Autodesk Fusion 360 part; units mm, degrees
(part 24 of 28)
  line L1680 (23.605, 52.1978, -1.4859) -> (23.605, 54.4322, -1.4859)
  line L1681 (23.605, 54.4322, -1.4859) -> (23.6209, 54.5414, -1.4859)
  line L1682 (23.6209, 54.5414, -1.4859) -> (23.6763, 54.6546, -1.4859)
  line L1683 (23.6763, 54.6546, -1.4859) -> (23.7654, 54.7437, -1.4859)
  line L1684 (23.7654, 54.7437, -1.4859) -> (23.8786, 54.7991, -1.4859)
  line L1685 (23.8786, 54.7991, -1.4859) -> (23.9878, 54.815, -1.4859)
  line L1686 (23.9878, 54.815, -1.4859) -> (25.6722, 54.815, -1.4859)
  line L1687 (25.6722, 54.815, -1.4859) -> (25.7814, 54.7991, -1.4859)
  line L1688 (60.7064, 54.7991, -1.4859) -> (60.8196, 54.7437, -1.4859)
  line L1689 (60.8196, 54.7437, -1.4859) -> (60.9087, 54.6546, -1.4859)
  line L1690 (60.9087, 54.6546, -1.4859) -> (60.9641, 54.5414, -1.4859)
  line L1691 (60.9641, 54.5414, -1.4859) -> (60.98, 54.4322, -1.4859)
  line L1692 (60.98, 54.4322, -1.4859) -> (60.98, 52.1978, -1.4859)
  line L1693 (60.98, 52.1978, -1.4859) -> (60.9641, 52.0886, -1.4859)
  line L1694 (60.9641, 52.0886, -1.4859) -> (60.9087, 51.9754, -1.4859)
  line L1695 (60.9087, 51.9754, -1.4859) -> (60.8196, 51.8863, -1.4859)
  line L1696 (60.8196, 51.8863, -1.4859) -> (60.7064, 51.8309, -1.4859)
  line L1697 (60.7064, 51.8309, -1.4859) -> (60.5972, 51.815, -1.4859)
  line L1698 (60.5972, 51.815, -1.4859) -> (58.9128, 51.815, -1.4859)
  line L1699 (58.9128, 51.815, -1.4859) -> (58.8036, 51.8309, -1.4859)
  line L1700 (58.8036, 51.8309, -1.4859) -> (58.6904, 51.8863, -1.4859)
  line L1701 (58.6904, 51.8863, -1.4859) -> (58.6013, 51.9754, -1.4859)
  line L1702 (58.6013, 51.9754, -1.4859) -> (58.5459, 52.0886, -1.4859)
  line L1703 (58.5459, 52.0886, -1.4859) -> (58.53, 52.1978, -1.4859)
  line L1704 (58.53, 52.1978, -1.4859) -> (58.53, 54.4322, -1.4859)
  line L1705 (58.53, 54.4322, -1.4859) -> (58.5459, 54.5414, -1.4859)
  line L1706 (58.5459, 54.5414, -1.4859) -> (58.6013, 54.6546, -1.4859)
  line L1707 (58.6013, 54.6546, -1.4859) -> (58.6904, 54.7437, -1.4859)
  line L1708 (58.6904, 54.7437, -1.4859) -> (58.8036, 54.7991, -1.4859)
  line L1709 (58.8036, 54.7991, -1.4859) -> (58.9128, 54.815, -1.4859)
  line L1710 (58.9128, 54.815, -1.4859) -> (60.5972, 54.815, -1.4859)
  line L1711 (60.5972, 54.815, -1.4859) -> (60.7064, 54.7991, -1.4859)
  line L1712 (95.6314, 54.7991, -1.4859) -> (95.7446, 54.7437, -1.4859)
  line L1713 (95.7446, 54.7437, -1.4859) -> (95.8337, 54.6546, -1.4859)
  line L1714 (95.8337, 54.6546, -1.4859) -> (95.8891, 54.5414, -1.4859)
  line L1715 (95.8891, 54.5414, -1.4859) -> (95.905, 54.4322, -1.4859)
  line L1716 (95.905, 54.4322, -1.4859) -> (95.905, 52.1978, -1.4859)
  line L1717 (95.905, 52.1978, -1.4859) -> (95.8891, 52.0886, -1.4859)
  line L1718 (95.8891, 52.0886, -1.4859) -> (95.8337, 51.9754, -1.4859)
  line L1719 (95.8337, 51.9754, -1.4859) -> (95.7446, 51.8863, -1.4859)
  line L1720 (95.7446, 51.8863, -1.4859) -> (95.6314, 51.8309, -1.4859)
  line L1721 (95.6314, 51.8309, -1.4859) -> (95.5222, 51.815, -1.4859)
  line L1722 (95.5222, 51.815, -1.4859) -> (93.8378, 51.815, -1.4859)
  line L1723 (93.8378, 51.815, -1.4859) -> (93.7286, 51.8309, -1.4859)
  line L1724 (93.7286, 51.8309, -1.4859) -> (93.6154, 51.8863, -1.4859)
  line L1725 (93.6154, 51.8863, -1.4859) -> (93.5263, 51.9754, -1.4859)
  line L1726 (93.5263, 51.9754, -1.4859) -> (93.4709, 52.0886, -1.4859)
  line L1727 (93.4709, 52.0886, -1.4859) -> (93.455, 52.1978, -1.4859)
  line L1728 (93.455, 52.1978, -1.4859) -> (93.455, 54.4322, -1.4859)
  line L1729 (93.455, 54.4322, -1.4859) -> (93.4709, 54.5414, -1.4859)
  line L1730 (93.4709, 54.5414, -1.4859) -> (93.5263, 54.6546, -1.4859)
  line L1731 (93.5263, 54.6546, -1.4859) -> (93.6154, 54.7437, -1.4859)
  line L1732 (93.6154, 54.7437, -1.4859) -> (93.7286, 54.7991, -1.4859)
  line L1733 (93.7286, 54.7991, -1.4859) -> (93.8378, 54.815, -1.4859)
  line L1734 (93.8378, 54.815, -1.4859) -> (95.5222, 54.815, -1.4859)
  line L1735 (95.5222, 54.815, -1.4859) -> (95.6314, 54.7991, -1.4859)
  line L1736 (130.5564, 54.7991, -1.4859) -> (130.6696, 54.7437, -1.4859)
  line L1737 (130.6696, 54.7437, -1.4859) -> (130.7587, 54.6546, -1.4859)
  line L1738 (130.7587, 54.6546, -1.4859) -> (130.8141, 54.5414, -1.4859)
  line L1739 (130.8141, 54.5414, -1.4859) -> (130.83, 54.4322, -1.4859)
  line L1740 (130.83, 54.4322, -1.4859) -> (130.83, 52.1978, -1.4859)
  line L1741 (130.83, 52.1978, -1.4859) -> (130.8141, 52.0886, -1.4859)
  line L1742 (130.8141, 52.0886, -1.4859) -> (130.7587, 51.9754, -1.4859)
  line L1743 (130.7587, 51.9754, -1.4859) -> (130.6696, 51.8863, -1.4859)
  line L1744 (130.6696, 51.8863, -1.4859) -> (130.5564, 51.8309, -1.4859)
  line L1745 (130.5564, 51.8309, -1.4859) -> (130.4472, 51.815, -1.4859)
  line L1746 (130.4472, 51.815, -1.4859) -> (128.7628, 51.815, -1.4859)
  line L1747 (128.7628, 51.815, -1.4859) -> (128.6536, 51.8309, -1.4859)
  line L1748 (128.6536, 51.8309, -1.4859) -> (128.5404, 51.8863, -1.4859)
  line L1749 (128.5404, 51.8863, -1.4859) -> (128.4513, 51.9754, -1.4859)
  line L1750 (128.4513, 51.9754, -1.4859) -> (128.3959, 52.0886, -1.4859)
  line L1751 (128.3959, 52.0886, -1.4859) -> (128.38, 52.1978, -1.4859)
  line L1752 (128.38, 52.1978, -1.4859) -> (128.38, 54.4322, -1.4859)
  line L1753 (128.38, 54.4322, -1.4859) -> (128.3959, 54.5414, -1.4859)
  line L1754 (128.3959, 54.5414, -1.4859) -> (128.4513, 54.6546, -1.4859)
  line L1755 (128.4513, 54.6546, -1.4859) -> (128.5404, 54.7437, -1.4859)
  line L1756 (128.5404, 54.7437, -1.4859) -> (128.6536, 54.7991, -1.4859)
  line L1757 (128.6536, 54.7991, -1.4859) -> (128.7628, 54.815, -1.4859)
  line L1758 (128.7628, 54.815, -1.4859) -> (130.4472, 54.815, -1.4859)
  line L1759 (130.4472, 54.815, -1.4859) -> (130.5564, 54.7991, -1.4859)
  line L1760 (27.616, 54.7812, -1.4859) -> (27.7988, 54.7218, -1.4859)
  line L1761 (27.7988, 54.7218, -1.4859) -> (27.9701, 54.6345, -1.4859)
  line L1762 (27.9701, 54.6345, -1.4859) -> (28.1256, 54.5215, -1.4859)
  line L1763 (28.1256, 54.5215, -1.4859) -> (28.2615, 54.3856, -1.4859)
  line L1764 (28.2615, 54.3856, -1.4859) -> (28.3745, 54.2301, -1.4859)
  line L1765 (28.3745, 54.2301, -1.4859) -> (28.4618, 54.0588, -1.4859)
  line L1766 (28.4618, 54.0588, -1.4859) -> (28.5212, 53.876, -1.4859)
  line L1767 (28.5212, 53.876, -1.4859) -> (28.5512, 53.6861, -1.4859)
  line L1768 (28.5512, 53.6861, -1.4859) -> (28.555, 53.59, -1.4859)
  line L1769 (28.555, 53.59, -1.4859) -> (28.555, 53.04, -1.4859)
  line L1770 (28.555, 53.04, -1.4859) -> (28.5512, 52.9439, -1.4859)
  line L1771 (28.5512, 52.9439, -1.4859) -> (28.5212, 52.754, -1.4859)
  line L1772 (28.5212, 52.754, -1.4859) -> (28.4618, 52.5712, -1.4859)
  line L1773 (28.4618, 52.5712, -1.4859) -> (28.3745, 52.3999, -1.4859)
  line L1774 (28.3745, 52.3999, -1.4859) -> (28.2615, 52.2444, -1.4859)
  line L1775 (28.2615, 52.2444, -1.4859) -> (28.1256, 52.1085, -1.4859)
  line L1776 (28.1256, 52.1085, -1.4859) -> (27.9701, 51.9955, -1.4859)
  line L1777 (27.9701, 51.9955, -1.4859) -> (27.7988, 51.9082, -1.4859)
  line L1778 (27.7988, 51.9082, -1.4859) -> (27.616, 51.8488, -1.4859)
  line L1779 (27.616, 51.8488, -1.4859) -> (27.4261, 51.8188, -1.4859)
  line L1780 (27.4261, 51.8188, -1.4859) -> (27.2339, 51.8188, -1.4859)
  line L1781 (27.2339, 51.8188, -1.4859) -> (27.044, 51.8488, -1.4859)
  line L1782 (27.044, 51.8488, -1.4859) -> (26.8612, 51.9082, -1.4859)
  line L1783 (26.8612, 51.9082, -1.4859) -> (26.6899, 51.9955, -1.4859)
  line L1784 (26.6899, 51.9955, -1.4859) -> (26.5344, 52.1085, -1.4859)
  line L1785 (26.5344, 52.1085, -1.4859) -> (26.3985, 52.2444, -1.4859)
  line L1786 (26.3985, 52.2444, -1.4859) -> (26.2855, 52.3999, -1.4859)
  line L1787 (26.2855, 52.3999, -1.4859) -> (26.1982, 52.5712, -1.4859)
  line L1788 (26.1982, 52.5712, -1.4859) -> (26.1388, 52.754, -1.4859)
  line L1789 (26.1388, 52.754, -1.4859) -> (26.1088, 52.9439, -1.4859)
  line L1790 (26.1088, 52.9439, -1.4859) -> (26.105, 53.04, -1.4859)
  line L1791 (26.105, 53.04, -1.4859) -> (26.105, 53.59, -1.4859)
  line L1792 (26.105, 53.59, -1.4859) -> (26.1088, 53.6861, -1.4859)
  line L1793 (26.1088, 53.6861, -1.4859) -> (26.1388, 53.876, -1.4859)
  line L1794 (26.1388, 53.876, -1.4859) -> (26.1982, 54.0588, -1.4859)
  line L1795 (26.1982, 54.0588, -1.4859) -> (26.2855, 54.2301, -1.4859)
  line L1796 (26.2855, 54.2301, -1.4859) -> (26.3985, 54.3856, -1.4859)
  line L1797 (26.3985, 54.3856, -1.4859) -> (26.5344, 54.5215, -1.4859)
  line L1798 (26.5344, 54.5215, -1.4859) -> (26.6899, 54.6345, -1.4859)
  line L1799 (26.6899, 54.6345, -1.4859) -> (26.8612, 54.7218, -1.4859)
  line L1800 (26.8612, 54.7218, -1.4859) -> (27.044, 54.7812, -1.4859)
  line L1801 (27.044, 54.7812, -1.4859) -> (27.2339, 54.8112, -1.4859)
  line L1802 (27.2339, 54.8112, -1.4859) -> (27.4261, 54.8112, -1.4859)
  line L1803 (27.4261, 54.8112, -1.4859) -> (27.616, 54.7812, -1.4859)
  line L1804 (62.541, 54.7812, -1.4859) -> (62.7238, 54.7218, -1.4859)
  line L1805 (62.7238, 54.7218, -1.4859) -> (62.8951, 54.6345, -1.4859)
  line L1806 (62.8951, 54.6345, -1.4859) -> (63.0506, 54.5215, -1.4859)
  line L1807 (63.0506, 54.5215, -1.4859) -> (63.1865, 54.3856, -1.4859)
  line L1808 (63.1865, 54.3856, -1.4859) -> (63.2995, 54.2301, -1.4859)
  line L1809 (63.2995, 54.2301, -1.4859) -> (63.3868, 54.0588, -1.4859)
  line L1810 (63.3868, 54.0588, -1.4859) -> (63.4462, 53.876, -1.4859)
  line L1811 (63.4462, 53.876, -1.4859) -> (63.4762, 53.6861, -1.4859)
  line L1812 (63.4762, 53.6861, -1.4859) -> (63.48, 53.59, -1.4859)
  line L1813 (63.48, 53.59, -1.4859) -> (63.48, 53.04, -1.4859)
  line L1814 (63.48, 53.04, -1.4859) -> (63.4762, 52.9439, -1.4859)
  line L1815 (63.4762, 52.9439, -1.4859) -> (63.4462, 52.754, -1.4859)
  line L1816 (63.4462, 52.754, -1.4859) -> (63.3868, 52.5712, -1.4859)
  line L1817 (63.3868, 52.5712, -1.4859) -> (63.2995, 52.3999, -1.4859)
  line L1818 (63.2995, 52.3999, -1.4859) -> (63.1865, 52.2444, -1.4859)
  line L1819 (63.1865, 52.2444, -1.4859) -> (63.0506, 52.1085, -1.4859)
  line L1820 (63.0506, 52.1085, -1.4859) -> (62.8951, 51.9955, -1.4859)
  line L1821 (62.8951, 51.9955, -1.4859) -> (62.7238, 51.9082, -1.4859)
  line L1822 (62.7238, 51.9082, -1.4859) -> (62.541, 51.8488, -1.4859)
  line L1823 (62.541, 51.8488, -1.4859) -> (62.3511, 51.8188, -1.4859)
  line L1824 (62.3511, 51.8188, -1.4859) -> (62.1589, 51.8188, -1.4859)
  line L1825 (62.1589, 51.8188, -1.4859) -> (61.969, 51.8488, -1.4859)
  line L1826 (61.969, 51.8488, -1.4859) -> (61.7862, 51.9082, -1.4859)
  line L1827 (61.7862, 51.9082, -1.4859) -> (61.6149, 51.9955, -1.4859)
  line L1828 (61.6149, 51.9955, -1.4859) -> (61.4594, 52.1085, -1.4859)
  line L1829 (61.4594, 52.1085, -1.4859) -> (61.3235, 52.2444, -1.4859)
  line L1830 (61.3235, 52.2444, -1.4859) -> (61.2105, 52.3999, -1.4859)
  line L1831 (61.2105, 52.3999, -1.4859) -> (61.1232, 52.5712, -1.4859)
  line L1832 (61.1232, 52.5712, -1.4859) -> (61.0638, 52.754, -1.4859)
  line L1833 (61.0638, 52.754, -1.4859) -> (61.0338, 52.9439, -1.4859)
  line L1834 (61.0338, 52.9439, -1.4859) -> (61.03, 53.04, -1.4859)
  line L1835 (61.03, 53.04, -1.4859) -> (61.03, 53.59, -1.4859)
  line L1836 (61.03, 53.59, -1.4859) -> (61.0338, 53.6861, -1.4859)
  line L1837 (61.0338, 53.6861, -1.4859) -> (61.0638, 53.876, -1.4859)
  line L1838 (61.0638, 53.876, -1.4859) -> (61.1232, 54.0588, -1.4859)
  line L1839 (61.1232, 54.0588, -1.4859) -> (61.2105, 54.2301, -1.4859)
  line L1840 (61.2105, 54.2301, -1.4859) -> (61.3235, 54.3856, -1.4859)
  line L1841 (61.3235, 54.3856, -1.4859) -> (61.4594, 54.5215, -1.4859)
  line L1842 (61.4594, 54.5215, -1.4859) -> (61.6149, 54.6345, -1.4859)
  line L1843 (61.6149, 54.6345, -1.4859) -> (61.7862, 54.7218, -1.4859)
  line L1844 (61.7862, 54.7218, -1.4859) -> (61.969, 54.7812, -1.4859)
  line L1845 (61.969, 54.7812, -1.4859) -> (62.1589, 54.8112, -1.4859)
  line L1846 (62.1589, 54.8112, -1.4859) -> (62.3511, 54.8112, -1.4859)
  line L1847 (62.3511, 54.8112, -1.4859) -> (62.541, 54.7812, -1.4859)
  line L1848 (97.466, 54.7812, -1.4859) -> (97.6488, 54.7218, -1.4859)
  line L1849 (97.6488, 54.7218, -1.4859) -> (97.8201, 54.6345, -1.4859)
  line L1850 (97.8201, 54.6345, -1.4859) -> (97.9756, 54.5215, -1.4859)
  line L1851 (97.9756, 54.5215, -1.4859) -> (98.1115, 54.3856, -1.4859)
  line L1852 (98.1115, 54.3856, -1.4859) -> (98.2245, 54.2301, -1.4859)
  line L1853 (98.2245, 54.2301, -1.4859) -> (98.3118, 54.0588, -1.4859)
  line L1854 (98.3118, 54.0588, -1.4859) -> (98.3712, 53.876, -1.4859)
  line L1855 (98.3712, 53.876, -1.4859) -> (98.4012, 53.6861, -1.4859)
  line L1856 (98.4012, 53.6861, -1.4859) -> (98.405, 53.59, -1.4859)
  line L1857 (98.405, 53.59, -1.4859) -> (98.405, 53.04, -1.4859)
  line L1858 (98.405, 53.04, -1.4859) -> (98.4012, 52.9439, -1.4859)
  line L1859 (98.4012, 52.9439, -1.4859) -> (98.3712, 52.754, -1.4859)
  line L1860 (98.3712, 52.754, -1.4859) -> (98.3118, 52.5712, -1.4859)
  line L1861 (98.3118, 52.5712, -1.4859) -> (98.2245, 52.3999, -1.4859)
  line L1862 (98.2245, 52.3999, -1.4859) -> (98.1115, 52.2444, -1.4859)
  line L1863 (98.1115, 52.2444, -1.4859) -> (97.9756, 52.1085, -1.4859)
  line L1864 (97.9756, 52.1085, -1.4859) -> (97.8201, 51.9955, -1.4859)
  line L1865 (97.8201, 51.9955, -1.4859) -> (97.6488, 51.9082, -1.4859)
  line L1866 (97.6488, 51.9082, -1.4859) -> (97.466, 51.8488, -1.4859)
  line L1867 (97.466, 51.8488, -1.4859) -> (97.2761, 51.8188, -1.4859)
  line L1868 (97.2761, 51.8188, -1.4859) -> (97.0839, 51.8188, -1.4859)
  line L1869 (97.0839, 51.8188, -1.4859) -> (96.894, 51.8488, -1.4859)
  line L1870 (96.894, 51.8488, -1.4859) -> (96.7112, 51.9082, -1.4859)
  line L1871 (96.7112, 51.9082, -1.4859) -> (96.5399, 51.9955, -1.4859)
  line L1872 (96.5399, 51.9955, -1.4859) -> (96.3844, 52.1085, -1.4859)
  line L1873 (96.3844, 52.1085, -1.4859) -> (96.2485, 52.2444, -1.4859)
  line L1874 (96.2485, 52.2444, -1.4859) -> (96.1355, 52.3999, -1.4859)
  line L1875 (96.1355, 52.3999, -1.4859) -> (96.0482, 52.5712, -1.4859)
  line L1876 (96.0482, 52.5712, -1.4859) -> (95.9888, 52.754, -1.4859)
  line L1877 (95.9888, 52.754, -1.4859) -> (95.9588, 52.9439, -1.4859)
  line L1878 (95.9588, 52.9439, -1.4859) -> (95.955, 53.04, -1.4859)
  line L1879 (95.955, 53.04, -1.4859) -> (95.955, 53.59, -1.4859)
  line L1880 (95.955, 53.59, -1.4859) -> (95.9588, 53.6861, -1.4859)
  line L1881 (95.9588, 53.6861, -1.4859) -> (95.9888, 53.876, -1.4859)
  line L1882 (95.9888, 53.876, -1.4859) -> (96.0482, 54.0588, -1.4859)
  line L1883 (96.0482, 54.0588, -1.4859) -> (96.1355, 54.2301, -1.4859)
  line L1884 (96.1355, 54.2301, -1.4859) -> (96.2485, 54.3856, -1.4859)
  line L1885 (96.2485, 54.3856, -1.4859) -> (96.3844, 54.5215, -1.4859)
  line L1886 (96.3844, 54.5215, -1.4859) -> (96.5399, 54.6345, -1.4859)
  line L1887 (96.5399, 54.6345, -1.4859) -> (96.7112, 54.7218, -1.4859)
  line L1888 (96.7112, 54.7218, -1.4859) -> (96.894, 54.7812, -1.4859)
  line L1889 (96.894, 54.7812, -1.4859) -> (97.0839, 54.8112, -1.4859)
  line L1890 (97.0839, 54.8112, -1.4859) -> (97.2761, 54.8112, -1.4859)
  line L1891 (97.2761, 54.8112, -1.4859) -> (97.466, 54.7812, -1.4859)
  line L1892 (132.391, 54.7812, -1.4859) -> (132.5738, 54.7218, -1.4859)
  line L1893 (132.5738, 54.7218, -1.4859) -> (132.7451, 54.6345, -1.4859)
  line L1894 (132.7451, 54.6345, -1.4859) -> (132.9006, 54.5215, -1.4859)
  line L1895 (132.9006, 54.5215, -1.4859) -> (133.0365, 54.3856, -1.4859)
  line L1896 (133.0365, 54.3856, -1.4859) -> (133.1495, 54.2301, -1.4859)
  line L1897 (133.1495, 54.2301, -1.4859) -> (133.2368, 54.0588, -1.4859)
  line L1898 (133.2368, 54.0588, -1.4859) -> (133.2962, 53.876, -1.4859)
  line L1899 (133.2962, 53.876, -1.4859) -> (133.3262, 53.6861, -1.4859)
  line L1900 (133.3262, 53.6861, -1.4859) -> (133.33, 53.59, -1.4859)
  line L1901 (133.33, 53.59, -1.4859) -> (133.33, 53.04, -1.4859)
  line L1902 (133.33, 53.04, -1.4859) -> (133.3262, 52.9439, -1.4859)
  line L1903 (133.3262, 52.9439, -1.4859) -> (133.2962, 52.754, -1.4859)
  line L1904 (133.2962, 52.754, -1.4859) -> (133.2368, 52.5712, -1.4859)
  line L1905 (133.2368, 52.5712, -1.4859) -> (133.1495, 52.3999, -1.4859)
  line L1906 (133.1495, 52.3999, -1.4859) -> (133.0365, 52.2444, -1.4859)
  line L1907 (133.0365, 52.2444, -1.4859) -> (132.9006, 52.1085, -1.4859)
  line L1908 (132.9006, 52.1085, -1.4859) -> (132.7451, 51.9955, -1.4859)
  line L1909 (132.7451, 51.9955, -1.4859) -> (132.5738, 51.9082, -1.4859)
  line L1910 (132.5738, 51.9082, -1.4859) -> (132.391, 51.8488, -1.4859)
  line L1911 (132.391, 51.8488, -1.4859) -> (132.2011, 51.8188, -1.4859)
  line L1912 (132.2011, 51.8188, -1.4859) -> (132.0089, 51.8188, -1.4859)
  line L1913 (132.0089, 51.8188, -1.4859) -> (131.819, 51.8488, -1.4859)
  line L1914 (131.819, 51.8488, -1.4859) -> (131.6362, 51.9082, -1.4859)
  line L1915 (131.6362, 51.9082, -1.4859) -> (131.4649, 51.9955, -1.4859)
  line L1916 (131.4649, 51.9955, -1.4859) -> (131.3094, 52.1085, -1.4859)
  line L1917 (131.3094, 52.1085, -1.4859) -> (131.1735, 52.2444, -1.4859)
  line L1918 (131.1735, 52.2444, -1.4859) -> (131.0605, 52.3999, -1.4859)
  line L1919 (131.0605, 52.3999, -1.4859) -> (130.9732, 52.5712, -1.4859)
  line L1920 (130.9732, 52.5712, -1.4859) -> (130.9138, 52.754, -1.4859)
  line L1921 (130.9138, 52.754, -1.4859) -> (130.8838, 52.9439, -1.4859)
  line L1922 (130.8838, 52.9439, -1.4859) -> (130.88, 53.04, -1.4859)
  line L1923 (130.88, 53.04, -1.4859) -> (130.88, 53.59, -1.4859)
  line L1924 (130.88, 53.59, -1.4859) -> (130.8838, 53.6861, -1.4859)
  line L1925 (130.8838, 53.6861, -1.4859) -> (130.9138, 53.876, -1.4859)
  line L1926 (130.9138, 53.876, -1.4859) -> (130.9732, 54.0588, -1.4859)
  line L1927 (130.9732, 54.0588, -1.4859) -> (131.0605, 54.2301, -1.4859)
  line L1928 (131.0605, 54.2301, -1.4859) -> (131.1735, 54.3856, -1.4859)
  line L1929 (131.1735, 54.3856, -1.4859) -> (131.3094, 54.5215, -1.4859)
  line L1930 (131.3094, 54.5215, -1.4859) -> (131.4649, 54.6345, -1.4859)
  line L1931 (131.4649, 54.6345, -1.4859) -> (131.6362, 54.7218, -1.4859)
  line L1932 (131.6362, 54.7218, -1.4859) -> (131.819, 54.7812, -1.4859)
  line L1933 (131.819, 54.7812, -1.4859) -> (132.0089, 54.8112, -1.4859)
  line L1934 (132.0089, 54.8112, -1.4859) -> (132.2011, 54.8112, -1.4859)
  line L1935 (132.2011, 54.8112, -1.4859) -> (132.391, 54.7812, -1.4859)
  line L1936 (14.6061, 55.2122, -1.4859) -> (14.7193, 55.1569, -1.4859)
  line L1937 (14.7193, 55.1569, -1.4859) -> (14.8084, 55.0677, -1.4859)
  line L1938 (14.8084, 55.0677, -1.4859) -> (14.8638, 54.9545, -1.4859)
  line L1939 (14.8638, 54.9545, -1.4859) -> (14.8797, 54.8453, -1.4859)
  line L1940 (14.8797, 54.8453, -1.4859) -> (14.8797, 52.6109, -1.4859)
  line L1941 (14.8797, 52.6109, -1.4859) -> (14.8638, 52.5017, -1.4859)
  line L1942 (14.8638, 52.5017, -1.4859) -> (14.8084, 52.3885, -1.4859)
  line L1943 (14.8084, 52.3885, -1.4859) -> (14.7193, 52.2994, -1.4859)
  line L1944 (14.7193, 52.2994, -1.4859) -> (14.6061, 52.244, -1.4859)
  line L1945 (14.6061, 52.244, -1.4859) -> (14.4969, 52.2281, -1.4859)
  line L1946 (14.4969, 52.2281, -1.4859) -> (12.8125, 52.2281, -1.4859)
  line L1947 (12.8125, 52.2281, -1.4859) -> (12.7033, 52.244, -1.4859)
  line L1948 (12.7033, 52.244, -1.4859) -> (12.5901, 52.2994, -1.4859)
  line L1949 (12.5901, 52.2994, -1.4859) -> (12.5009, 52.3885, -1.4859)
  line L1950 (12.5009, 52.3885, -1.4859) -> (12.4456, 52.5017, -1.4859)
  line L1951 (12.4456, 52.5017, -1.4859) -> (12.4297, 52.6109, -1.4859)
  line L1952 (12.4297, 52.6109, -1.4859) -> (12.4297, 54.8453, -1.4859)
  line L1953 (12.4297, 54.8453, -1.4859) -> (12.4456, 54.9545, -1.4859)
  line L1954 (12.4456, 54.9545, -1.4859) -> (12.5009, 55.0677, -1.4859)
  line L1955 (12.5009, 55.0677, -1.4859) -> (12.5901, 55.1569, -1.4859)
  line L1956 (12.5901, 55.1569, -1.4859) -> (12.7033, 55.2122, -1.4859)
  line L1957 (12.7033, 55.2122, -1.4859) -> (12.8125, 55.2281, -1.4859)
  line L1958 (12.8125, 55.2281, -1.4859) -> (14.4969, 55.2281, -1.4859)
  line L1959 (14.4969, 55.2281, -1.4859) -> (14.6061, 55.2122, -1.4859)
  line L1960 (49.5311, 55.2122, -1.4859) -> (49.6443, 55.1569, -1.4859)
  line L1961 (49.6443, 55.1569, -1.4859) -> (49.7334, 55.0677, -1.4859)
  line L1962 (49.7334, 55.0677, -1.4859) -> (49.7888, 54.9545, -1.4859)
  line L1963 (49.7888, 54.9545, -1.4859) -> (49.8047, 54.8453, -1.4859)
  line L1964 (49.8047, 54.8453, -1.4859) -> (49.8047, 52.6109, -1.4859)
  line L1965 (49.8047, 52.6109, -1.4859) -> (49.7888, 52.5017, -1.4859)
  line L1966 (49.7888, 52.5017, -1.4859) -> (49.7334, 52.3885, -1.4859)
  line L1967 (49.7334, 52.3885, -1.4859) -> (49.6443, 52.2994, -1.4859)
  line L1968 (49.6443, 52.2994, -1.4859) -> (49.5311, 52.244, -1.4859)
  line L1969 (49.5311, 52.244, -1.4859) -> (49.4219, 52.2281, -1.4859)
  line L1970 (49.4219, 52.2281, -1.4859) -> (47.7375, 52.2281, -1.4859)
  line L1971 (47.7375, 52.2281, -1.4859) -> (47.6283, 52.244, -1.4859)
  line L1972 (47.6283, 52.244, -1.4859) -> (47.5151, 52.2994, -1.4859)
  line L1973 (47.5151, 52.2994, -1.4859) -> (47.4259, 52.3885, -1.4859)
  line L1974 (47.4259, 52.3885, -1.4859) -> (47.3706, 52.5017, -1.4859)
  line L1975 (47.3706, 52.5017, -1.4859) -> (47.3547, 52.6109, -1.4859)
  line L1976 (47.3547, 52.6109, -1.4859) -> (47.3547, 54.8453, -1.4859)
  line L1977 (47.3547, 54.8453, -1.4859) -> (47.3706, 54.9545, -1.4859)
  line L1978 (47.3706, 54.9545, -1.4859) -> (47.4259, 55.0677, -1.4859)
  line L1979 (47.4259, 55.0677, -1.4859) -> (47.5151, 55.1569, -1.4859)
  line L1980 (47.5151, 55.1569, -1.4859) -> (47.6283, 55.2122, -1.4859)
  line L1981 (47.6283, 55.2122, -1.4859) -> (47.7375, 55.2281, -1.4859)
  line L1982 (47.7375, 55.2281, -1.4859) -> (49.4219, 55.2281, -1.4859)
  line L1983 (49.4219, 55.2281, -1.4859) -> (49.5311, 55.2122, -1.4859)
  line L1984 (84.4561, 55.2122, -1.4859) -> (84.5693, 55.1569, -1.4859)
  line L1985 (84.5693, 55.1569, -1.4859) -> (84.6584, 55.0677, -1.4859)
  line L1986 (84.6584, 55.0677, -1.4859) -> (84.7138, 54.9545, -1.4859)
  line L1987 (84.7138, 54.9545, -1.4859) -> (84.7297, 54.8453, -1.4859)
  line L1988 (84.7297, 54.8453, -1.4859) -> (84.7297, 52.6109, -1.4859)
  line L1989 (84.7297, 52.6109, -1.4859) -> (84.7138, 52.5017, -1.4859)
  line L1990 (84.7138, 52.5017, -1.4859) -> (84.6584, 52.3885, -1.4859)
  line L1991 (84.6584, 52.3885, -1.4859) -> (84.5693, 52.2994, -1.4859)
  line L1992 (84.5693, 52.2994, -1.4859) -> (84.4561, 52.244, -1.4859)
  line L1993 (84.4561, 52.244, -1.4859) -> (84.3469, 52.2281, -1.4859)
  line L1994 (84.3469, 52.2281, -1.4859) -> (82.6625, 52.2281, -1.4859)
  line L1995 (82.6625, 52.2281, -1.4859) -> (82.5533, 52.244, -1.4859)
  line L1996 (82.5533, 52.244, -1.4859) -> (82.4401, 52.2994, -1.4859)
  line L1997 (82.4401, 52.2994, -1.4859) -> (82.3509, 52.3885, -1.4859)
  line L1998 (82.3509, 52.3885, -1.4859) -> (82.2956, 52.5017, -1.4859)
  line L1999 (82.2956, 52.5017, -1.4859) -> (82.2797, 52.6109, -1.4859)
  line L2000 (82.2797, 52.6109, -1.4859) -> (82.2797, 54.8453, -1.4859)
  line L2001 (82.2797, 54.8453, -1.4859) -> (82.2956, 54.9545, -1.4859)
  line L2002 (82.2956, 54.9545, -1.4859) -> (82.3509, 55.0677, -1.4859)
  line L2003 (82.3509, 55.0677, -1.4859) -> (82.4401, 55.1569, -1.4859)
  line L2004 (82.4401, 55.1569, -1.4859) -> (82.5533, 55.2122, -1.4859)
  line L2005 (82.5533, 55.2122, -1.4859) -> (82.6625, 55.2281, -1.4859)
  line L2006 (82.6625, 55.2281, -1.4859) -> (84.3469, 55.2281, -1.4859)
  line L2007 (84.3469, 55.2281, -1.4859) -> (84.4561, 55.2122, -1.4859)
  line L2008 (119.3811, 55.2122, -1.4859) -> (119.4943, 55.1569, -1.4859)
  line L2009 (119.4943, 55.1569, -1.4859) -> (119.5834, 55.0677, -1.4859)
  line L2010 (119.5834, 55.0677, -1.4859) -> (119.6388, 54.9545, -1.4859)
  line L2011 (119.6388, 54.9545, -1.4859) -> (119.6547, 54.8453, -1.4859)
  line L2012 (119.6547, 54.8453, -1.4859) -> (119.6547, 52.6109, -1.4859)
  line L2013 (119.6547, 52.6109, -1.4859) -> (119.6388, 52.5017, -1.4859)
  line L2014 (119.6388, 52.5017, -1.4859) -> (119.5834, 52.3885, -1.4859)
  line L2015 (119.5834, 52.3885, -1.4859) -> (119.4943, 52.2994, -1.4859)
  line L2016 (119.4943, 52.2994, -1.4859) -> (119.3811, 52.244, -1.4859)
  line L2017 (119.3811, 52.244, -1.4859) -> (119.2719, 52.2281, -1.4859)
  line L2018 (119.2719, 52.2281, -1.4859) -> (117.5875, 52.2281, -1.4859)
  line L2019 (117.5875, 52.2281, -1.4859) -> (117.4783, 52.244, -1.4859)
  line L2020 (117.4783, 52.244, -1.4859) -> (117.3651, 52.2994, -1.4859)
  line L2021 (117.3651, 52.2994, -1.4859) -> (117.2759, 52.3885, -1.4859)
  line L2022 (117.2759, 52.3885, -1.4859) -> (117.2206, 52.5017, -1.4859)
  line L2023 (117.2206, 52.5017, -1.4859) -> (117.2047, 52.6109, -1.4859)
  line L2024 (117.2047, 52.6109, -1.4859) -> (117.2047, 54.8453, -1.4859)
  line L2025 (117.2047, 54.8453, -1.4859) -> (117.2206, 54.9545, -1.4859)
  line L2026 (117.2206, 54.9545, -1.4859) -> (117.2759, 55.0677, -1.4859)
  line L2027 (117.2759, 55.0677, -1.4859) -> (117.3651, 55.1569, -1.4859)
  line L2028 (117.3651, 55.1569, -1.4859) -> (117.4783, 55.2122, -1.4859)
  line L2029 (117.4783, 55.2122, -1.4859) -> (117.5875, 55.2281, -1.4859)
  line L2030 (117.5875, 55.2281, -1.4859) -> (119.2719, 55.2281, -1.4859)
  line L2031 (119.2719, 55.2281, -1.4859) -> (119.3811, 55.2122, -1.4859)
  line L2032 (16.4407, 55.1943, -1.4859) -> (16.6235, 55.1349, -1.4859)
  line L2033 (16.6235, 55.1349, -1.4859) -> (16.7947, 55.0476, -1.4859)
  line L2034 (16.7947, 55.0476, -1.4859) -> (16.9503, 54.9346, -1.4859)
  line L2035 (16.9503, 54.9346, -1.4859) -> (17.0862, 54.7987, -1.4859)
  line L2036 (17.0862, 54.7987, -1.4859) -> (17.1992, 54.6432, -1.4859)
  line L2037 (17.1992, 54.6432, -1.4859) -> (17.2864, 54.4719, -1.4859)
  line L2038 (17.2864, 54.4719, -1.4859) -> (17.3458, 54.2891, -1.4859)
  line L2039 (17.3458, 54.2891, -1.4859) -> (17.3759, 54.0992, -1.4859)
  line L2040 (17.3759, 54.0992, -1.4859) -> (17.3797, 54.0031, -1.4859)
  line L2041 (17.3797, 54.0031, -1.4859) -> (17.3797, 53.4531, -1.4859)
  line L2042 (17.3797, 53.4531, -1.4859) -> (17.3759, 53.357, -1.4859)
  line L2043 (17.3759, 53.357, -1.4859) -> (17.3458, 53.1671, -1.4859)
  line L2044 (17.3458, 53.1671, -1.4859) -> (17.2864, 52.9843, -1.4859)
  line L2045 (17.2864, 52.9843, -1.4859) -> (17.1992, 52.8131, -1.4859)
  line L2046 (17.1992, 52.8131, -1.4859) -> (17.0862, 52.6575, -1.4859)
  line L2047 (17.0862, 52.6575, -1.4859) -> (16.9503, 52.5216, -1.4859)
  line L2048 (16.9503, 52.5216, -1.4859) -> (16.7947, 52.4086, -1.4859)
  line L2049 (16.7947, 52.4086, -1.4859) -> (16.6235, 52.3214, -1.4859)
  line L2050 (16.6235, 52.3214, -1.4859) -> (16.4407, 52.262, -1.4859)
  line L2051 (16.4407, 52.262, -1.4859) -> (16.2508, 52.2319, -1.4859)
  line L2052 (16.2508, 52.2319, -1.4859) -> (16.0586, 52.2319, -1.4859)
  line L2053 (16.0586, 52.2319, -1.4859) -> (15.8687, 52.262, -1.4859)
  line L2054 (15.8687, 52.262, -1.4859) -> (15.6859, 52.3214, -1.4859)
  line L2055 (15.6859, 52.3214, -1.4859) -> (15.5146, 52.4086, -1.4859)
  line L2056 (15.5146, 52.4086, -1.4859) -> (15.3591, 52.5216, -1.4859)
  line L2057 (15.3591, 52.5216, -1.4859) -> (15.2232, 52.6575, -1.4859)
  line L2058 (15.2232, 52.6575, -1.4859) -> (15.1102, 52.8131, -1.4859)
  line L2059 (15.1102, 52.8131, -1.4859) -> (15.0229, 52.9843, -1.4859)
  line L2060 (15.0229, 52.9843, -1.4859) -> (14.9635, 53.1671, -1.4859)
  line L2061 (14.9635, 53.1671, -1.4859) -> (14.9335, 53.357, -1.4859)
  line L2062 (14.9335, 53.357, -1.4859) -> (14.9297, 53.4531, -1.4859)
  line L2063 (14.9297, 53.4531, -1.4859) -> (14.9297, 54.0031, -1.4859)
  line L2064 (14.9297, 54.0031, -1.4859) -> (14.9335, 54.0992, -1.4859)
  line L2065 (14.9335, 54.0992, -1.4859) -> (14.9635, 54.2891, -1.4859)
  line L2066 (14.9635, 54.2891, -1.4859) -> (15.0229, 54.4719, -1.4859)
  line L2067 (15.0229, 54.4719, -1.4859) -> (15.1102, 54.6432, -1.4859)
  line L2068 (15.1102, 54.6432, -1.4859) -> (15.2232, 54.7987, -1.4859)
  line L2069 (15.2232, 54.7987, -1.4859) -> (15.3591, 54.9346, -1.4859)
  line L2070 (15.3591, 54.9346, -1.4859) -> (15.5146, 55.0476, -1.4859)
  line L2071 (15.5146, 55.0476, -1.4859) -> (15.6859, 55.1349, -1.4859)
  line L2072 (15.6859, 55.1349, -1.4859) -> (15.8687, 55.1943, -1.4859)
  line L2073 (15.8687, 55.1943, -1.4859) -> (16.0586, 55.2243, -1.4859)
  line L2074 (16.0586, 55.2243, -1.4859) -> (16.2508, 55.2243, -1.4859)
  line L2075 (16.2508, 55.2243, -1.4859) -> (16.4407, 55.1943, -1.4859)
  line L2076 (51.3657, 55.1943, -1.4859) -> (51.5485, 55.1349, -1.4859)
  line L2077 (51.5485, 55.1349, -1.4859) -> (51.7197, 55.0476, -1.4859)
  line L2078 (51.7197, 55.0476, -1.4859) -> (51.8753, 54.9346, -1.4859)
  line L2079 (51.8753, 54.9346, -1.4859) -> (52.0112, 54.7987, -1.4859)
  line L2080 (52.0112, 54.7987, -1.4859) -> (52.1242, 54.6432, -1.4859)
  line L2081 (52.1242, 54.6432, -1.4859) -> (52.2114, 54.4719, -1.4859)
  line L2082 (52.2114, 54.4719, -1.4859) -> (52.2708, 54.2891, -1.4859)
  line L2083 (52.2708, 54.2891, -1.4859) -> (52.3009, 54.0992, -1.4859)
  line L2084 (52.3009, 54.0992, -1.4859) -> (52.3047, 54.0031, -1.4859)
  line L2085 (52.3047, 54.0031, -1.4859) -> (52.3047, 53.4531, -1.4859)
  line L2086 (52.3047, 53.4531, -1.4859) -> (52.3009, 53.357, -1.4859)
  line L2087 (52.3009, 53.357, -1.4859) -> (52.2708, 53.1671, -1.4859)
  line L2088 (52.2708, 53.1671, -1.4859) -> (52.2114, 52.9843, -1.4859)
  line L2089 (52.2114, 52.9843, -1.4859) -> (52.1242, 52.8131, -1.4859)
  line L2090 (52.1242, 52.8131, -1.4859) -> (52.0112, 52.6575, -1.4859)
  line L2091 (52.0112, 52.6575, -1.4859) -> (51.8753, 52.5216, -1.4859)
  line L2092 (51.8753, 52.5216, -1.4859) -> (51.7197, 52.4086, -1.4859)
  line L2093 (51.7197, 52.4086, -1.4859) -> (51.5485, 52.3214, -1.4859)
  line L2094 (51.5485, 52.3214, -1.4859) -> (51.3657, 52.262, -1.4859)
  line L2095 (51.3657, 52.262, -1.4859) -> (51.1758, 52.2319, -1.4859)
  line L2096 (51.1758, 52.2319, -1.4859) -> (50.9836, 52.2319, -1.4859)
  line L2097 (50.9836, 52.2319, -1.4859) -> (50.7937, 52.262, -1.4859)
  line L2098 (50.7937, 52.262, -1.4859) -> (50.6109, 52.3214, -1.4859)
  line L2099 (50.6109, 52.3214, -1.4859) -> (50.4396, 52.4086, -1.4859)
  line L2100 (50.4396, 52.4086, -1.4859) -> (50.2841, 52.5216, -1.4859)
  line L2101 (50.2841, 52.5216, -1.4859) -> (50.1482, 52.6575, -1.4859)
  line L2102 (50.1482, 52.6575, -1.4859) -> (50.0352, 52.8131, -1.4859)
  line L2103 (50.0352, 52.8131, -1.4859) -> (49.9479, 52.9843, -1.4859)
  line L2104 (49.9479, 52.9843, -1.4859) -> (49.8885, 53.1671, -1.4859)
  line L2105 (49.8885, 53.1671, -1.4859) -> (49.8585, 53.357, -1.4859)
  line L2106 (49.8585, 53.357, -1.4859) -> (49.8547, 53.4531, -1.4859)
  line L2107 (49.8547, 53.4531, -1.4859) -> (49.8547, 54.0031, -1.4859)
  line L2108 (49.8547, 54.0031, -1.4859) -> (49.8585, 54.0992, -1.4859)
  line L2109 (49.8585, 54.0992, -1.4859) -> (49.8885, 54.2891, -1.4859)
  line L2110 (49.8885, 54.2891, -1.4859) -> (49.9479, 54.4719, -1.4859)
  line L2111 (49.9479, 54.4719, -1.4859) -> (50.0352, 54.6432, -1.4859)
  line L2112 (50.0352, 54.6432, -1.4859) -> (50.1482, 54.7987, -1.4859)
  line L2113 (50.1482, 54.7987, -1.4859) -> (50.2841, 54.9346, -1.4859)
  line L2114 (50.2841, 54.9346, -1.4859) -> (50.4396, 55.0476, -1.4859)
  line L2115 (50.4396, 55.0476, -1.4859) -> (50.6109, 55.1349, -1.4859)
  line L2116 (50.6109, 55.1349, -1.4859) -> (50.7937, 55.1943, -1.4859)
  line L2117 (50.7937, 55.1943, -1.4859) -> (50.9836, 55.2243, -1.4859)
  line L2118 (50.9836, 55.2243, -1.4859) -> (51.1758, 55.2243, -1.4859)
  line L2119 (51.1758, 55.2243, -1.4859) -> (51.3657, 55.1943, -1.4859)
  line L2120 (86.2907, 55.1943, -1.4859) -> (86.4735, 55.1349, -1.4859)
  line L2121 (86.4735, 55.1349, -1.4859) -> (86.6447, 55.0476, -1.4859)
  line L2122 (86.6447, 55.0476, -1.4859) -> (86.8003, 54.9346, -1.4859)
  line L2123 (86.8003, 54.9346, -1.4859) -> (86.9362, 54.7987, -1.4859)
  line L2124 (86.9362, 54.7987, -1.4859) -> (87.0492, 54.6432, -1.4859)
  line L2125 (87.0492, 54.6432, -1.4859) -> (87.1364, 54.4719, -1.4859)
  line L2126 (87.1364, 54.4719, -1.4859) -> (87.1958, 54.2891, -1.4859)
  line L2127 (87.1958, 54.2891, -1.4859) -> (87.2259, 54.0992, -1.4859)
  line L2128 (87.2259, 54.0992, -1.4859) -> (87.2297, 54.0031, -1.4859)
  line L2129 (87.2297, 54.0031, -1.4859) -> (87.2297, 53.4531, -1.4859)
  line L2130 (87.2297, 53.4531, -1.4859) -> (87.2259, 53.357, -1.4859)
  line L2131 (87.2259, 53.357, -1.4859) -> (87.1958, 53.1671, -1.4859)
  line L2132 (87.1958, 53.1671, -1.4859) -> (87.1364, 52.9843, -1.4859)
  line L2133 (87.1364, 52.9843, -1.4859) -> (87.0492, 52.8131, -1.4859)
  line L2134 (87.0492, 52.8131, -1.4859) -> (86.9362, 52.6575, -1.4859)
  line L2135 (86.9362, 52.6575, -1.4859) -> (86.8003, 52.5216, -1.4859)
  line L2136 (86.8003, 52.5216, -1.4859) -> (86.6447, 52.4086, -1.4859)
  line L2137 (86.6447, 52.4086, -1.4859) -> (86.4735, 52.3214, -1.4859)
  line L2138 (86.4735, 52.3214, -1.4859) -> (86.2907, 52.262, -1.4859)
  line L2139 (86.2907, 52.262, -1.4859) -> (86.1008, 52.2319, -1.4859)
  line L2140 (86.1008, 52.2319, -1.4859) -> (85.9086, 52.2319, -1.4859)
  line L2141 (85.9086, 52.2319, -1.4859) -> (85.7187, 52.262, -1.4859)
  line L2142 (85.7187, 52.262, -1.4859) -> (85.5359, 52.3214, -1.4859)
  line L2143 (85.5359, 52.3214, -1.4859) -> (85.3646, 52.4086, -1.4859)
  line L2144 (85.3646, 52.4086, -1.4859) -> (85.2091, 52.5216, -1.4859)
  line L2145 (85.2091, 52.5216, -1.4859) -> (85.0732, 52.6575, -1.4859)
  line L2146 (85.0732, 52.6575, -1.4859) -> (84.9602, 52.8131, -1.4859)
  line L2147 (84.9602, 52.8131, -1.4859) -> (84.8729, 52.9843, -1.4859)
  line L2148 (84.8729, 52.9843, -1.4859) -> (84.8135, 53.1671, -1.4859)
  line L2149 (84.8135, 53.1671, -1.4859) -> (84.7835, 53.357, -1.4859)
  line L2150 (84.7835, 53.357, -1.4859) -> (84.7797, 53.4531, -1.4859)
  line L2151 (84.7797, 53.4531, -1.4859) -> (84.7797, 54.0031, -1.4859)
  line L2152 (84.7797, 54.0031, -1.4859) -> (84.7835, 54.0992, -1.4859)
  line L2153 (84.7835, 54.0992, -1.4859) -> (84.8135, 54.2891, -1.4859)
  line L2154 (84.8135, 54.2891, -1.4859) -> (84.8729, 54.4719, -1.4859)
  line L2155 (84.8729, 54.4719, -1.4859) -> (84.9602, 54.6432, -1.4859)
  line L2156 (84.9602, 54.6432, -1.4859) -> (85.0732, 54.7987, -1.4859)
  line L2157 (85.0732, 54.7987, -1.4859) -> (85.2091, 54.9346, -1.4859)
  line L2158 (85.2091, 54.9346, -1.4859) -> (85.3646, 55.0476, -1.4859)
  line L2159 (85.3646, 55.0476, -1.4859) -> (85.5359, 55.1349, -1.4859)
  line L2160 (85.5359, 55.1349, -1.4859) -> (85.7187, 55.1943, -1.4859)
  line L2161 (85.7187, 55.1943, -1.4859) -> (85.9086, 55.2243, -1.4859)
  line L2162 (85.9086, 55.2243, -1.4859) -> (86.1008, 55.2243, -1.4859)
  line L2163 (86.1008, 55.2243, -1.4859) -> (86.2907, 55.1943, -1.4859)
  line L2164 (121.2157, 55.1943, -1.4859) -> (121.3985, 55.1349, -1.4859)
  line L2165 (121.3985, 55.1349, -1.4859) -> (121.5697, 55.0476, -1.4859)
  line L2166 (121.5697, 55.0476, -1.4859) -> (121.7253, 54.9346, -1.4859)
  line L2167 (121.7253, 54.9346, -1.4859) -> (121.8612, 54.7987, -1.4859)
  line L2168 (121.8612, 54.7987, -1.4859) -> (121.9742, 54.6432, -1.4859)
  line L2169 (121.9742, 54.6432, -1.4859) -> (122.0614, 54.4719, -1.4859)
  line L2170 (122.0614, 54.4719, -1.4859) -> (122.1208, 54.2891, -1.4859)
  line L2171 (122.1208, 54.2891, -1.4859) -> (122.1509, 54.0992, -1.4859)
  line L2172 (122.1509, 54.0992, -1.4859) -> (122.1547, 54.0031, -1.4859)
  line L2173 (122.1547, 54.0031, -1.4859) -> (122.1547, 53.4531, -1.4859)
  line L2174 (122.1547, 53.4531, -1.4859) -> (122.1509, 53.357, -1.4859)
  line L2175 (122.1509, 53.357, -1.4859) -> (122.1208, 53.1671, -1.4859)
  line L2176 (122.1208, 53.1671, -1.4859) -> (122.0614, 52.9843, -1.4859)
  line L2177 (122.0614, 52.9843, -1.4859) -> (121.9742, 52.8131, -1.4859)
  line L2178 (121.9742, 52.8131, -1.4859) -> (121.8612, 52.6575, -1.4859)
  line L2179 (121.8612, 52.6575, -1.4859) -> (121.7253, 52.5216, -1.4859)
  line L2180 (121.7253, 52.5216, -1.4859) -> (121.5697, 52.4086, -1.4859)
  line L2181 (121.5697, 52.4086, -1.4859) -> (121.3985, 52.3214, -1.4859)
  line L2182 (121.3985, 52.3214, -1.4859) -> (121.2157, 52.262, -1.4859)
  line L2183 (121.2157, 52.262, -1.4859) -> (121.0258, 52.2319, -1.4859)
  line L2184 (121.0258, 52.2319, -1.4859) -> (120.8336, 52.2319, -1.4859)
  line L2185 (120.8336, 52.2319, -1.4859) -> (120.6437, 52.262, -1.4859)
  line L2186 (120.6437, 52.262, -1.4859) -> (120.4609, 52.3214, -1.4859)
  line L2187 (120.4609, 52.3214, -1.4859) -> (120.2896, 52.4086, -1.4859)
  line L2188 (120.2896, 52.4086, -1.4859) -> (120.1341, 52.5216, -1.4859)
  line L2189 (120.1341, 52.5216, -1.4859) -> (119.9982, 52.6575, -1.4859)
  line L2190 (119.9982, 52.6575, -1.4859) -> (119.8852, 52.8131, -1.4859)
  line L2191 (119.8852, 52.8131, -1.4859) -> (119.7979, 52.9843, -1.4859)
  line L2192 (119.7979, 52.9843, -1.4859) -> (119.7385, 53.1671, -1.4859)
  line L2193 (119.7385, 53.1671, -1.4859) -> (119.7085, 53.357, -1.4859)
  line L2194 (119.7085, 53.357, -1.4859) -> (119.7047, 53.4531, -1.4859)
  line L2195 (119.7047, 53.4531, -1.4859) -> (119.7047, 54.0031, -1.4859)
  line L2196 (119.7047, 54.0031, -1.4859) -> (119.7085, 54.0992, -1.4859)
  line L2197 (119.7085, 54.0992, -1.4859) -> (119.7385, 54.2891, -1.4859)
  line L2198 (119.7385, 54.2891, -1.4859) -> (119.7979, 54.4719, -1.4859)
  line L2199 (119.7979, 54.4719, -1.4859) -> (119.8852, 54.6432, -1.4859)
  line L2200 (119.8852, 54.6432, -1.4859) -> (119.9982, 54.7987, -1.4859)
  line L2201 (119.9982, 54.7987, -1.4859) -> (120.1341, 54.9346, -1.4859)
  line L2202 (120.1341, 54.9346, -1.4859) -> (120.2896, 55.0476, -1.4859)
  line L2203 (120.2896, 55.0476, -1.4859) -> (120.4609, 55.1349, -1.4859)
  line L2204 (120.4609, 55.1349, -1.4859) -> (120.6437, 55.1943, -1.4859)
  line L2205 (120.6437, 55.1943, -1.4859) -> (120.8336, 55.2243, -1.4859)
  line L2206 (120.8336, 55.2243, -1.4859) -> (121.0258, 55.2243, -1.4859)
  line L2207 (121.0258, 55.2243, -1.4859) -> (121.2157, 55.1943, -1.4859)
  line L2208 (33.0348, 62.5322, -1.4859) -> (33.2214, 62.4716, -1.4859)
  line L2209 (33.2214, 62.4716, -1.4859) -> (33.3962, 62.3825, -1.4859)
  line L2210 (33.3962, 62.3825, -1.4859) -> (33.5549, 62.2672, -1.4859)
  line L2211 (33.5549, 62.2672, -1.4859) -> (33.6936, 62.1286, -1.4859)
  line L2212 (33.6936, 62.1286, -1.4859) -> (33.8088, 61.9699, -1.4859)
  line L2213 (33.8088, 61.9699, -1.4859) -> (33.8979, 61.7951, -1.4859)
  line L2214 (33.8979, 61.7951, -1.4859) -> (33.9585, 61.6085, -1.4859)
  line L2215 (33.9585, 61.6085, -1.4859) -> (33.9892, 61.4148, -1.4859)
  line L2216 (33.9892, 61.4148, -1.4859) -> (33.993, 61.3167, -1.4859)
  line L2217 (33.993, 61.3167, -1.4859) -> (33.993, 60.8167, -1.4859)
  line L2218 (33.993, 60.8167, -1.4859) -> (33.9892, 60.7187, -1.4859)
  line L2219 (33.9892, 60.7187, -1.4859) -> (33.9585, 60.5249, -1.4859)
  line L2220 (33.9585, 60.5249, -1.4859) -> (33.8979, 60.3384, -1.4859)
  line L2221 (33.8979, 60.3384, -1.4859) -> (33.8088, 60.1636, -1.4859)
  line L2222 (33.8088, 60.1636, -1.4859) -> (33.6936, 60.0049, -1.4859)
  line L2223 (33.6936, 60.0049, -1.4859) -> (33.5549, 59.8662, -1.4859)
  line L2224 (33.5549, 59.8662, -1.4859) -> (33.3962, 59.7509, -1.4859)
  line L2225 (33.3962, 59.7509, -1.4859) -> (33.2214, 59.6619, -1.4859)
  line L2226 (33.2214, 59.6619, -1.4859) -> (33.0348, 59.6013, -1.4859)
  line L2227 (33.0348, 59.6013, -1.4859) -> (32.8411, 59.5706, -1.4859)
  line L2228 (32.8411, 59.5706, -1.4859) -> (32.645, 59.5706, -1.4859)
  line L2229 (32.645, 59.5706, -1.4859) -> (32.4512, 59.6013, -1.4859)
  line L2230 (32.4512, 59.6013, -1.4859) -> (32.2647, 59.6619, -1.4859)
  line L2231 (32.2647, 59.6619, -1.4859) -> (32.0899, 59.7509, -1.4859)
  line L2232 (32.0899, 59.7509, -1.4859) -> (31.9312, 59.8662, -1.4859)
  line L2233 (31.9312, 59.8662, -1.4859) -> (31.7925, 60.0049, -1.4859)
  line L2234 (31.7925, 60.0049, -1.4859) -> (31.6772, 60.1636, -1.4859)
  line L2235 (31.6772, 60.1636, -1.4859) -> (31.5882, 60.3384, -1.4859)
  line L2236 (31.5882, 60.3384, -1.4859) -> (31.5276, 60.5249, -1.4859)
  line L2237 (31.5276, 60.5249, -1.4859) -> (31.4969, 60.7187, -1.4859)
  line L2238 (31.4969, 60.7187, -1.4859) -> (31.493, 60.8167, -1.4859)
  line L2239 (31.493, 60.8167, -1.4859) -> (31.493, 61.3167, -1.4859)
  line L2240 (31.493, 61.3167, -1.4859) -> (31.4969, 61.4148, -1.4859)
  line L2241 (31.4969, 61.4148, -1.4859) -> (31.5276, 61.6085, -1.4859)
  line L2242 (31.5276, 61.6085, -1.4859) -> (31.5882, 61.7951, -1.4859)
  line L2243 (31.5882, 61.7951, -1.4859) -> (31.6772, 61.9699, -1.4859)
  line L2244 (31.6772, 61.9699, -1.4859) -> (31.7925, 62.1286, -1.4859)
  line L2245 (31.7925, 62.1286, -1.4859) -> (31.9312, 62.2672, -1.4859)
  line L2246 (31.9312, 62.2672, -1.4859) -> (32.0899, 62.3825, -1.4859)
  line L2247 (32.0899, 62.3825, -1.4859) -> (32.2647, 62.4716, -1.4859)
  line L2248 (32.2647, 62.4716, -1.4859) -> (32.4512, 62.5322, -1.4859)
  line L2249 (32.4512, 62.5322, -1.4859) -> (32.645, 62.5629, -1.4859)
  line L2250 (32.645, 62.5629, -1.4859) -> (32.8411, 62.5629, -1.4859)
  line L2251 (32.8411, 62.5629, -1.4859) -> (33.0348, 62.5322, -1.4859)
  line L2252 (67.9598, 62.5322, -1.4859) -> (68.1464, 62.4716, -1.4859)
  line L2253 (68.1464, 62.4716, -1.4859) -> (68.3212, 62.3825, -1.4859)
  line L2254 (68.3212, 62.3825, -1.4859) -> (68.4799, 62.2672, -1.4859)
  line L2255 (68.4799, 62.2672, -1.4859) -> (68.6185, 62.1286, -1.4859)
  line L2256 (68.6185, 62.1286, -1.4859) -> (68.7338, 61.9699, -1.4859)
  line L2257 (68.7338, 61.9699, -1.4859) -> (68.8229, 61.7951, -1.4859)
  line L2258 (68.8229, 61.7951, -1.4859) -> (68.8835, 61.6085, -1.4859)
  line L2259 (68.8835, 61.6085, -1.4859) -> (68.9142, 61.4148, -1.4859)
  line L2260 (68.9142, 61.4148, -1.4859) -> (68.918, 61.3167, -1.4859)
  line L2261 (68.918, 61.3167, -1.4859) -> (68.918, 60.8167, -1.4859)
  line L2262 (68.918, 60.8167, -1.4859) -> (68.9142, 60.7187, -1.4859)
  line L2263 (68.9142, 60.7187, -1.4859) -> (68.8835, 60.5249, -1.4859)
  line L2264 (68.8835, 60.5249, -1.4859) -> (68.8229, 60.3384, -1.4859)
  line L2265 (68.8229, 60.3384, -1.4859) -> (68.7338, 60.1636, -1.4859)
  line L2266 (68.7338, 60.1636, -1.4859) -> (68.6185, 60.0049, -1.4859)
  line L2267 (68.6185, 60.0049, -1.4859) -> (68.4799, 59.8662, -1.4859)
  line L2268 (68.4799, 59.8662, -1.4859) -> (68.3212, 59.7509, -1.4859)
  line L2269 (68.3212, 59.7509, -1.4859) -> (68.1464, 59.6619, -1.4859)
  line L2270 (68.1464, 59.6619, -1.4859) -> (67.9598, 59.6013, -1.4859)
  line L2271 (67.9598, 59.6013, -1.4859) -> (67.7661, 59.5706, -1.4859)
  line L2272 (67.7661, 59.5706, -1.4859) -> (67.57, 59.5706, -1.4859)
  line L2273 (67.57, 59.5706, -1.4859) -> (67.3762, 59.6013, -1.4859)
  line L2274 (67.3762, 59.6013, -1.4859) -> (67.1897, 59.6619, -1.4859)
  line L2275 (67.1897, 59.6619, -1.4859) -> (67.0149, 59.7509, -1.4859)
  line L2276 (67.0149, 59.7509, -1.4859) -> (66.8562, 59.8662, -1.4859)
  line L2277 (66.8562, 59.8662, -1.4859) -> (66.7175, 60.0049, -1.4859)
  line L2278 (66.7175, 60.0049, -1.4859) -> (66.6022, 60.1636, -1.4859)
  line L2279 (66.6022, 60.1636, -1.4859) -> (66.5132, 60.3384, -1.4859)
  line L2280 (66.5132, 60.3384, -1.4859) -> (66.4526, 60.5249, -1.4859)
  line L2281 (66.4526, 60.5249, -1.4859) -> (66.4219, 60.7187, -1.4859)
  line L2282 (66.4219, 60.7187, -1.4859) -> (66.418, 60.8167, -1.4859)
  line L2283 (66.418, 60.8167, -1.4859) -> (66.418, 61.3167, -1.4859)
  line L2284 (66.418, 61.3167, -1.4859) -> (66.4219, 61.4148, -1.4859)
  line L2285 (66.4219, 61.4148, -1.4859) -> (66.4526, 61.6085, -1.4859)
  line L2286 (66.4526, 61.6085, -1.4859) -> (66.5132, 61.7951, -1.4859)
  line L2287 (66.5132, 61.7951, -1.4859) -> (66.6022, 61.9699, -1.4859)
  line L2288 (66.6022, 61.9699, -1.4859) -> (66.7175, 62.1286, -1.4859)
  line L2289 (66.7175, 62.1286, -1.4859) -> (66.8562, 62.2672, -1.4859)
  line L2290 (66.8562, 62.2672, -1.4859) -> (67.0149, 62.3825, -1.4859)
  line L2291 (67.0149, 62.3825, -1.4859) -> (67.1897, 62.4716, -1.4859)
  line L2292 (67.1897, 62.4716, -1.4859) -> (67.3762, 62.5322, -1.4859)
  line L2293 (67.3762, 62.5322, -1.4859) -> (67.57, 62.5629, -1.4859)
  line L2294 (67.57, 62.5629, -1.4859) -> (67.7661, 62.5629, -1.4859)
  line L2295 (67.7661, 62.5629, -1.4859) -> (67.9599, 62.5322, -1.4859)
  line L2296 (102.8849, 62.5322, -1.4859) -> (103.0714, 62.4716, -1.4859)
  line L2297 (103.0714, 62.4716, -1.4859) -> (103.2462, 62.3825, -1.4859)
  line L2298 (103.2462, 62.3825, -1.4859) -> (103.4049, 62.2672, -1.4859)
  line L2299 (103.4049, 62.2672, -1.4859) -> (103.5436, 62.1286, -1.4859)
  line L2300 (103.5436, 62.1286, -1.4859) -> (103.6588, 61.9699, -1.4859)
  line L2301 (103.6588, 61.9699, -1.4859) -> (103.7479, 61.7951, -1.4859)
  line L2302 (103.7479, 61.7951, -1.4859) -> (103.8085, 61.6085, -1.4859)
  line L2303 (103.8085, 61.6085, -1.4859) -> (103.8392, 61.4148, -1.4859)
  line L2304 (103.8392, 61.4148, -1.4859) -> (103.843, 61.3167, -1.4859)
  line L2305 (103.843, 61.3167, -1.4859) -> (103.843, 60.8167, -1.4859)
  line L2306 (103.843, 60.8167, -1.4859) -> (103.8392, 60.7187, -1.4859)
  line L2307 (103.8392, 60.7187, -1.4859) -> (103.8085, 60.5249, -1.4859)
  line L2308 (103.8085, 60.5249, -1.4859) -> (103.7479, 60.3384, -1.4859)
  line L2309 (103.7479, 60.3384, -1.4859) -> (103.6588, 60.1636, -1.4859)
  line L2310 (103.6588, 60.1636, -1.4859) -> (103.5436, 60.0049, -1.4859)
  line L2311 (103.5436, 60.0049, -1.4859) -> (103.4049, 59.8662, -1.4859)
  line L2312 (103.4049, 59.8662, -1.4859) -> (103.2462, 59.7509, -1.4859)
  line L2313 (103.2462, 59.7509, -1.4859) -> (103.0714, 59.6619, -1.4859)
  line L2314 (103.0714, 59.6619, -1.4859) -> (102.8848, 59.6013, -1.4859)
  line L2315 (102.8849, 59.6013, -1.4859) -> (102.6911, 59.5706, -1.4859)
  line L2316 (102.6911, 59.5706, -1.4859) -> (102.495, 59.5706, -1.4859)
  line L2317 (102.495, 59.5706, -1.4859) -> (102.3012, 59.6013, -1.4859)
  line L2318 (102.3012, 59.6013, -1.4859) -> (102.1147, 59.6619, -1.4859)
  line L2319 (102.1147, 59.6619, -1.4859) -> (101.9399, 59.7509, -1.4859)
  line L2320 (101.9399, 59.7509, -1.4859) -> (101.7812, 59.8662, -1.4859)
  line L2321 (101.7812, 59.8662, -1.4859) -> (101.6425, 60.0049, -1.4859)
  line L2322 (101.6425, 60.0049, -1.4859) -> (101.5272, 60.1636, -1.4859)
  line L2323 (101.5272, 60.1636, -1.4859) -> (101.4382, 60.3384, -1.4859)
  line L2324 (101.4382, 60.3384, -1.4859) -> (101.3776, 60.5249, -1.4859)
  line L2325 (101.3776, 60.5249, -1.4859) -> (101.3469, 60.7187, -1.4859)
  line L2326 (101.3469, 60.7187, -1.4859) -> (101.343, 60.8167, -1.4859)
  line L2327 (101.343, 60.8167, -1.4859) -> (101.343, 61.3167, -1.4859)
  line L2328 (101.343, 61.3167, -1.4859) -> (101.3469, 61.4148, -1.4859)
  line L2329 (101.3469, 61.4148, -1.4859) -> (101.3776, 61.6085, -1.4859)
  line L2330 (101.3776, 61.6085, -1.4859) -> (101.4382, 61.7951, -1.4859)
  line L2331 (101.4382, 61.7951, -1.4859) -> (101.5272, 61.9699, -1.4859)
  line L2332 (101.5272, 61.9699, -1.4859) -> (101.6425, 62.1286, -1.4859)
  line L2333 (101.6425, 62.1286, -1.4859) -> (101.7812, 62.2672, -1.4859)
  line L2334 (101.7812, 62.2672, -1.4859) -> (101.9399, 62.3825, -1.4859)
  line L2335 (101.9399, 62.3825, -1.4859) -> (102.1147, 62.4716, -1.4859)
  line L2336 (102.1147, 62.4716, -1.4859) -> (102.3012, 62.5322, -1.4859)
  line L2337 (102.3012, 62.5322, -1.4859) -> (102.495, 62.5629, -1.4859)
  line L2338 (102.495, 62.5629, -1.4859) -> (102.6911, 62.5629, -1.4859)
  line L2339 (102.6911, 62.5629, -1.4859) -> (102.8848, 62.5322, -1.4859)
  line L2340 (137.8098, 62.5322, -1.4859) -> (137.9964, 62.4716, -1.4859)
  line L2341 (137.9964, 62.4716, -1.4859) -> (138.1712, 62.3825, -1.4859)
  line L2342 (138.1712, 62.3825, -1.4859) -> (138.3299, 62.2672, -1.4859)
  line L2343 (138.3299, 62.2672, -1.4859) -> (138.4685, 62.1286, -1.4859)
  line L2344 (138.4685, 62.1286, -1.4859) -> (138.5838, 61.9699, -1.4859)
  line L2345 (138.5838, 61.9699, -1.4859) -> (138.6729, 61.7951, -1.4859)
  line L2346 (138.6729, 61.7951, -1.4859) -> (138.7335, 61.6085, -1.4859)
  line L2347 (138.7335, 61.6085, -1.4859) -> (138.7642, 61.4148, -1.4859)
  line L2348 (138.7642, 61.4148, -1.4859) -> (138.768, 61.3167, -1.4859)
  line L2349 (138.768, 61.3167, -1.4859) -> (138.768, 60.8167, -1.4859)
  line L2350 (138.768, 60.8167, -1.4859) -> (138.7642, 60.7187, -1.4859)
  line L2351 (138.7642, 60.7187, -1.4859) -> (138.7335, 60.5249, -1.4859)
  line L2352 (138.7335, 60.5249, -1.4859) -> (138.6729, 60.3384, -1.4859)
  line L2353 (138.6729, 60.3384, -1.4859) -> (138.5838, 60.1636, -1.4859)
  line L2354 (138.5838, 60.1636, -1.4859) -> (138.4685, 60.0049, -1.4859)
  line L2355 (138.4685, 60.0049, -1.4859) -> (138.3299, 59.8662, -1.4859)
  line L2356 (138.3299, 59.8662, -1.4859) -> (138.1712, 59.7509, -1.4859)
  line L2357 (138.1712, 59.7509, -1.4859) -> (137.9964, 59.6619, -1.4859)
  line L2358 (137.9964, 59.6619, -1.4859) -> (137.8099, 59.6013, -1.4859)
  line L2359 (137.8099, 59.6013, -1.4859) -> (137.6161, 59.5706, -1.4859)
  line L2360 (137.6161, 59.5706, -1.4859) -> (137.42, 59.5706, -1.4859)
  line L2361 (137.42, 59.5706, -1.4859) -> (137.2262, 59.6013, -1.4859)
  line L2362 (137.2262, 59.6013, -1.4859) -> (137.0397, 59.6619, -1.4859)
  line L2363 (137.0397, 59.6619, -1.4859) -> (136.8649, 59.7509, -1.4859)
  line L2364 (136.8649, 59.7509, -1.4859) -> (136.7062, 59.8662, -1.4859)
  line L2365 (136.7062, 59.8662, -1.4859) -> (136.5675, 60.0049, -1.4859)
  line L2366 (136.5675, 60.0049, -1.4859) -> (136.4522, 60.1636, -1.4859)
  line L2367 (136.4522, 60.1636, -1.4859) -> (136.3632, 60.3384, -1.4859)
  line L2368 (136.3632, 60.3384, -1.4859) -> (136.3026, 60.5249, -1.4859)
  line L2369 (136.3026, 60.5249, -1.4859) -> (136.2719, 60.7187, -1.4859)
  line L2370 (136.2719, 60.7187, -1.4859) -> (136.268, 60.8167, -1.4859)
  line L2371 (136.268, 60.8167, -1.4859) -> (136.268, 61.3167, -1.4859)